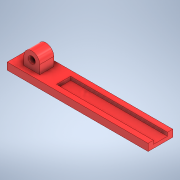
# Autodesk Inventor part: base
Saved by Autodesk Inventor 2022 (Build 260153000, 153)
## iProperties
Created: 2024-11-08
Part Number: base
Material: Generic
Document SubType Name: Modeling
Designer: Dell
Density: 1 g/cm^3
Appearance: Light Red
Author: Dell
Autodesk Inventor part; units mm, degrees
ref_plane "YZ Plane" through (0, 0, 0) normal (1, 0, 0) x (0, 1, 0)
ref_plane "XZ Plane" through (0, 0, 0) normal (0, 1, 0) x (-1, 0, 0)
ref_plane "XY Plane" through (0, 0, 0) normal (0, 0, 1) x (1, 0, 0)
sketch "Sketch1" plane through (0, 0, 0) normal (0, 0, 1) x (1, 0, 0)
  line L0 (0, 0) -> (-80, 0)
  line L1 (-80, 0) -> (-80, 4)
  line L2 (0, 4) -> (0, 0)
  circle A0 centre (-69.0304, 9) radius 2
  arc A1 (-64.5304, 9) -> (-73.5304, 9) centre (-69.0304, 9) ccw
  line L3 (-73.5304, 9) -> (-73.5304, 4)
  line L4 (-64.5304, 9) -> (-64.5304, 4)
  line L5 (-80, 4) -> (-73.5304, 4)
  line L6 (-64.5304, 4) -> (0, 4)
  dimension "d0" = 80
  dimension "d1" = 4
  dimension "d2" = 4
  dimension "d4" = 4.5
  constraints: 14 end point, 5 perpendicular, 3 parallel, 2 centre point, 2 point on circle, 2 tangent, 1 horizontal
  measures "d0" distance of L1.end L2.start
  measures "d1" distance of L0.end L1.end
  measures "d2" diameter of A0
  measures "d4" radius of A1
extrude "Extrusion1" add sketch "Sketch1" along normal blind 14
sketch "Sketch2" plane through (-64.5304, 4, 0) normal (0, 1, 0) x (1, 0, 0)
  line L0 (64.5304, -3) -> (9.5, -3)
  line L1 (9.5, -3) -> (9.5, -11)
  line L2 (9.5, -11) -> (64.5304, -11)
  line L3 (64.5304, -11) -> (64.5304, -3)
  line L4 (64.5304, 0) -> (0, 0) projected
  line L5 (0, 0) -> (0, -14) projected
  line L6 (0, 0) -> (0, -14) projected
  line L7 (-9, 0) -> (-9, -14) projected
  line L8 (0, 0) -> (-9, 0)
  line L9 (-9, 0) -> (-9, -3)
  line L10 (-9, -3) -> (0, -3)
  line L11 (0, -3) -> (0, 0)
  line L12 (0, -14) -> (-9, -14)
  line L13 (-9, -14) -> (-9, -11)
  line L14 (-9, -11) -> (0, -11)
  line L15 (0, -11) -> (0, -14)
  line L16 (64.5304, 0) -> (64.5304, -14) projected
  point P0 (-9, -11)
  dimension "d8" = 8
  dimension "d9" = 3
  dimension "d10" = 9.5
  dimension "d11" = 3
  dimension "d12" = 3
  constraints: 24 end point, 6 parallel, 3 horizontal, 3 perpendicular, 2 point on line, 1 collinear
  measures "d8" distance of L2.end L0.start
  measures "d9" distance between parallel lines of L4 L0
  measures "d10" distance between parallel lines of L5 L1
  measures "d11" distance of L9.end L8.end
  measures "d12" distance of L12.end L13.end
extrude "Extrusion2" cut sketch "Sketch2" along normal blind 10 contours L5 L10 L7 L8 | L5 L12 L7 L14
extrude "Extrusion3" cut sketch "Sketch2" against normal blind 2 contours L3 L2 L1 L0
body "Solid1"
